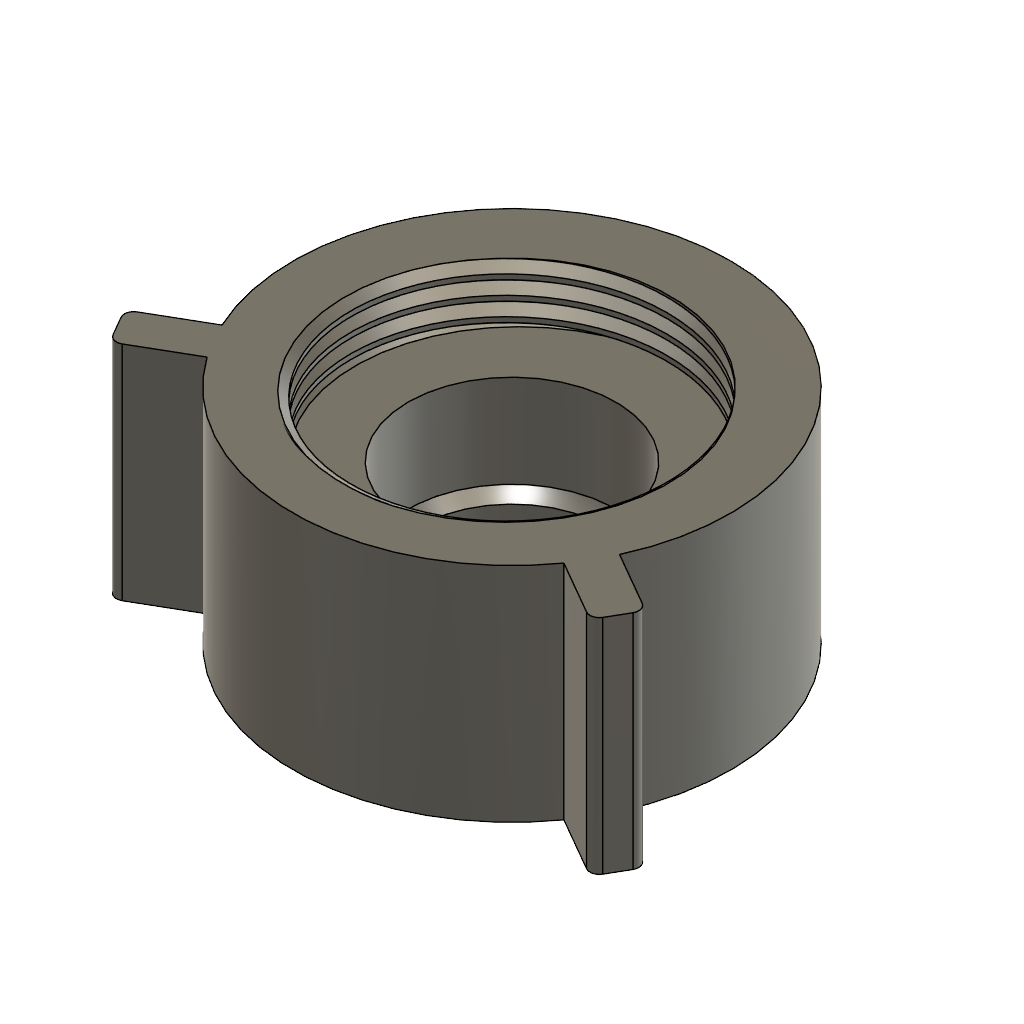
Lens Holder (Autodesk Fusion 360 design; units mm, degrees)
part number: 2026-10-19-12-24-29-766
Autodesk Fusion 360 part; units mm, degrees
sketch "Sketch1" plane through (0, 0, 0) normal (0, 1, 0) x (1, 0, 0)
  circle A0 centre (0, 0) radius 12 construction
  circle A1 centre (0, 0) radius 11.8
  line L0 (0, 15.6) -> (-13.51, -7.8) construction
  line L1 (-13.51, -7.8) -> (13.51, -7.8) construction
  line L2 (13.51, -7.8) -> (0, 15.6) construction
  line L3 (0, 0) -> (-13.51, -7.8) construction
  line L4 (0, 15.6) -> (0, 0) construction
  line L5 (0, 0) -> (13.51, -7.8) construction
  line L6 (-1.1, 15.6) -> (-1.1, 0)
  line L7 (1.1, 15.6) -> (1.1, 0)
  line L8 (-0.55, 0.9526) -> (-14.06, -6.8474)
  line L9 (0.55, -0.9526) -> (-12.96, -8.7526)
  line L10 (-14.06, -6.8474) -> (-13.51, -7.8)
  line L11 (-13.51, -7.8) -> (-12.96, -8.7526)
  line L12 (-1.1, 15.6) -> (0, 15.6)
  line L13 (1.1, 15.6) -> (0, 15.6)
  line L14 (-0.55, -0.9526) -> (12.96, -8.7526)
  line L15 (0.55, 0.9526) -> (14.06, -6.8474)
  line L16 (13.51, -7.8) -> (12.96, -8.7526)
  line L17 (14.06, -6.8474) -> (13.51, -7.8)
  circle A2 centre (0, 0) radius 5
  circle A3 centre (0, 0) radius 5.6
  circle A4 centre (0, 0) radius 9
  dimension "d2" = 24
  dimension "d6" = 15.6
  dimension "d8" = 1.1
  dimension "d16" = 10
  dimension "d17" = 11.2
  dimension "d19" = 18
  constraint coincident A0.centre A1.centre
  constraint vertical L4
  constraint perpendicular L3 L10
  constraint perpendicular L9 L11
  constraint perpendicular L4 L12
  constraint perpendicular L4 L13
  constraint equal L10 L12
  constraint equal L11 L12
  constraint equal L12 L13
  constraint perpendicular L14 L16
  constraint perpendicular L5 L17
  constraint equal L12 L17
  constraint equal L12 L16
  measures "d2" diameter of A0
  measures "d6" distance of L0.start A0.centre
  measures "d16" diameter of A2
  measures "d17" diameter of A3
  measures "d19" diameter of A4
extrude "Extrude1" add sketch "Sketch1" along normal blind 12 contours A1 L7 L15 A4 | A1 L6 L7 A4 | A1 L14 L15 L16 L17 | A1 L14 L15 A4 | A1 L6 L8 A4 | A1 L9 L14 A4 | A1 L8 L9 A4 | A1 L8 L9 L10 L11
extrude "Extrude3" add sketch "Sketch1" along normal blind 8.5 contours L7 L15 A3 A4 | L6 L7 A3 A4 | L14 L15 A3 A4 | L6 L8 A3 A4 | L9 L14 A3 A4 | L8 L9 A3 A4
extrude "Extrude2" add sketch "Sketch1" along normal blind 3.5 contours L7 L15 A3 A4 | L6 L7 A3 A4 | L14 L15 A3 A4 | L6 L8 A3 A4 | L7 L15 A2 A3 | L6 L7 A2 A3 | L9 L14 A3 A4 | L14 L15 A2 A3 | L8 L9 A3 A4 | L6 L8 A2 A3 | L9 L14 A2 A3 | L8 L9 A2 A3
sketch "Sketch2" plane through (0, 0, 0) normal (0, 0, 1) x (1, 0, 0)
  line L0 (-5.6, 3.5) -> (5.6, 3.5) construction
  line L1 (-5.6, 8.5) -> (5.6, 8.5) construction
  line L2 (-5, 3.5) -> (5, 3.5) construction
  line L3 (-5, 0) -> (5, 0) construction
  circle A0 through (-5, 3.5, 0) (2.5, 3.5, 4.3301) (2.5, 3.5, -4.3301) construction
  line L4 (0, 3.5) -> (0, 1.3) construction
  arc A1 (-5.6, 3.5) -> (5.6, 3.5) centre (0, 9.5273) ccw
  line L5 (-5.6, 3.5) -> (5.6, 3.5)
  line L6 (-5, 3.5) -> (-5, 2.9937)
  line L7 (5, 3.5) -> (5, 2.9937)
  constraint perpendicular L0 L4
  constraint coincident L4.end A1
  constraint coincident L0.end A1.end
  constraint coincident L0.start A1.start
  constraint coincident L2.start L6.start
  constraint coincident A1 L6.end
  constraint perpendicular L2 L6
  constraint coincident L2.end L7.start
  constraint coincident A1 L7.end
  constraint perpendicular L5 L7
revolve "Revolve1" cut sketch "Sketch2" angle 360 about axis through (0, 1.75, 0) along (0, 1, 0) contours A1 L5 L6 | A1 L5 L7
thread "Thread1" "ISO Metric profile 18.0 M18x1 M18x1 6H" major diameter 18.1522 minor diameter 17.0355 pitch 1 angle 60 modelled right hand crest width 0.2719 on face at (8.9888, 9.6667, -0.4486) crest through (8.5177, 8.75, 0)
ref_plane "WorkPlane1" through (0, 0, -11.9) normal (0, 0, 1) x (1, 0, 0)
sketch "Sketch3" plane through (0, 0, -11.9) normal (0, 0, 1) x (1, 0, 0)
  line L0 (0, 0) -> (0, 6) construction
  dimension "d37" = 6
  constraint coincident L0.start origin
  constraint vertical L0
  measures "d37" distance of L0.start L0.end
hole "Hole1" at (0, 6, -11.9) direction (0, 0, 1) diameter 3.4 depth 5 tip angle 180
fillet "Fillet1" radius 0.5 4 edges at (-12.96, 6, 8.7526) (-14.06, 6, 6.8474) (12.96, 6, 8.7526) (14.06, 6, 6.8474)
equation "tube_d = 24 mm"
equation "d2 = tube_d"
equation "d3 = -clearance"
equation "slot_d = 32 mm"
equation "clearance = 0.2 mm"
equation "d6 = ( slot_d ) / 2 - 2 * clearance"
equation "slot_w = 2.6 mm"
equation "d8 = ( slot_w ) / 2 - clearance"
equation "iris = 10 mm"
equation "lens_d = 11 mm"
equation "d16 = iris"
equation "d17 = lens_d + clearance"
equation "thread_d = 18 mm"
equation "d19 = thread_d"
equation "holder_h = 12 mm"
equation "d21 = holder_h"
equation "lens_h_min = 5 mm"
equation "d24 = ( holder_h - lens_h_min ) / 2"
equation "lens_h_max = 7 mm"
equation "d27 = holder_h - ( holder_h - lens_h_min ) / 2"
equation "d33 = ( lens_h_max - lens_h_min ) + clearance"
equation "d35 = -( tube_d - clearance ) / 2"
equation "d37 = holder_h / 2"
